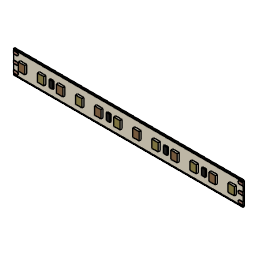
Key Light Housing (Autodesk Fusion 360 archive; units mm, degrees)
design "Yuji LED Single Strip"
Autodesk Fusion 360 part; units mm, degrees
sketch "Sketch1" plane through (0, 0, 0) normal (0, 1, 0) x (1, 0, 0)
  line L0 (0, 0) -> (100, 0)
  line L1 (100, 0) -> (100, -10)
  line L2 (100, -10) -> (0, -10)
  line L3 (0, -10) -> (0, 0)
  line L4 (2.95, -6.75) -> (5.75, -6.75)
  line L5 (5.75, -6.75) -> (5.75, -3.25)
  line L6 (5.75, -3.25) -> (2.95, -3.25)
  line L7 (2.95, -3.25) -> (2.95, -6.75)
  line L8 (11.25, -6.75) -> (14.05, -6.75)
  line L9 (14.05, -6.75) -> (14.05, -3.25)
  line L10 (14.05, -3.25) -> (11.25, -3.25)
  line L11 (11.25, -3.25) -> (11.25, -6.75)
  line L12 (0, -9.25) -> (1.5, -9.25)
  line L13 (1.5, -9.25) -> (1.5, -8) construction
  line L14 (1.5, -8) -> (0, -8)
  line L15 (0, -8) -> (0, -9.25)
  line L16 (0, -2) -> (1.5, -2)
  line L17 (1.5, -2) -> (1.5, -0.75) construction
  line L18 (1.5, -0.75) -> (0, -0.75)
  line L19 (0, -0.75) -> (0, -2)
  arc A0 (1.5, -9.25) -> (1.5, -8) centre (1.5, -8.625) ccw
  arc A1 (1.5, -2) -> (1.5, -0.75) centre (1.5, -1.375) ccw
  line L20 (50, -10) -> (50, 0) construction
  line L21 (0, -4.375) -> (1.5, -4.375)
  arc A2 (1.5, -5.625) -> (1.5, -4.375) centre (1.5, -5) ccw
  line L22 (0, -5.625) -> (0, -4.375)
  line L23 (1.5, -5.625) -> (0, -5.625)
  line L24 (1.5, -4.375) -> (1.5, -5.625) construction
  line L25 (100, -9.25) -> (98.5, -9.25)
  line L26 (98.5, -9.25) -> (98.5, -8) construction
  line L27 (98.5, -8) -> (100, -8)
  line L28 (100, -8) -> (100, -9.25)
  line L29 (98.5, -4.375) -> (100, -4.375)
  line L30 (100, -4.375) -> (100, -5.625)
  line L31 (100, -5.625) -> (98.5, -5.625)
  line L32 (98.5, -5.625) -> (98.5, -4.375) construction
  line L33 (98.5, -0.75) -> (100, -0.75)
  line L34 (100, -0.75) -> (100, -2)
  line L35 (100, -2) -> (98.5, -2)
  line L36 (98.5, -2) -> (98.5, -0.75) construction
  line L37 (0, -5) -> (2.95, -5) construction
  line L38 (5.75, -5) -> (11.25, -5) construction
  line L39 (19.55, -6.75) -> (22.35, -6.75)
  line L40 (22.35, -6.75) -> (22.35, -3.25)
  line L41 (22.35, -3.25) -> (19.55, -3.25)
  line L42 (19.55, -3.25) -> (19.55, -6.75)
  line L43 (27.85, -6.75) -> (30.65, -6.75)
  line L44 (30.65, -6.75) -> (30.65, -3.25)
  line L45 (30.65, -3.25) -> (27.85, -3.25)
  line L46 (27.85, -3.25) -> (27.85, -6.75)
  line L47 (36.15, -6.75) -> (38.95, -6.75)
  line L48 (38.95, -6.75) -> (38.95, -3.25)
  line L49 (38.95, -3.25) -> (36.15, -3.25)
  line L50 (36.15, -3.25) -> (36.15, -6.75)
  line L51 (14.05, -5) -> (19.55, -5) construction
  line L52 (22.35, -5) -> (27.85, -5) construction
  line L53 (30.65, -5) -> (36.15, -5) construction
  line L54 (72.15, -5) -> (77.65, -5) construction
  line L55 (80.45, -3.25) -> (77.65, -3.25)
  line L56 (69.35, -3.25) -> (69.35, -6.75)
  line L57 (44.45, -6.75) -> (47.25, -6.75)
  line L58 (52.75, -6.75) -> (55.55, -6.75)
  line L59 (55.55, -3.25) -> (52.75, -3.25)
  line L60 (63.85, -5) -> (69.35, -5) construction
  line L61 (47.25, -6.75) -> (47.25, -3.25)
  line L62 (77.65, -6.75) -> (80.45, -6.75)
  line L63 (52.75, -3.25) -> (52.75, -6.75)
  line L64 (61.05, -3.25) -> (61.05, -6.75)
  line L65 (44.45, -3.25) -> (44.45, -6.75)
  line L66 (63.85, -3.25) -> (61.05, -3.25)
  line L67 (61.05, -6.75) -> (63.85, -6.75)
  line L68 (72.15, -3.25) -> (69.35, -3.25)
  line L69 (63.85, -6.75) -> (63.85, -3.25)
  line L70 (72.15, -6.75) -> (72.15, -3.25)
  line L71 (80.45, -6.75) -> (80.45, -3.25)
  line L72 (77.65, -3.25) -> (77.65, -6.75)
  line L73 (55.55, -6.75) -> (55.55, -3.25)
  line L74 (69.35, -6.75) -> (72.15, -6.75)
  line L75 (47.25, -5) -> (52.75, -5) construction
  line L76 (47.25, -3.25) -> (44.45, -3.25)
  line L77 (55.55, -5) -> (61.05, -5) construction
  line L78 (38.95, -5) -> (44.45, -5) construction
  line L79 (97.05, -6.75) -> (97.05, -3.25)
  line L80 (88.75, -5) -> (94.25, -5) construction
  line L81 (85.95, -6.75) -> (88.75, -6.75)
  line L82 (94.25, -6.75) -> (97.05, -6.75)
  line L83 (97.05, -3.25) -> (94.25, -3.25)
  line L84 (88.75, -6.75) -> (88.75, -3.25)
  line L85 (85.95, -3.25) -> (85.95, -6.75)
  line L86 (94.25, -3.25) -> (94.25, -6.75)
  line L87 (88.75, -3.25) -> (85.95, -3.25)
  line L88 (80.45, -5) -> (85.95, -5) construction
  line L89 (97.05, -5) -> (100, -5) construction
  line L90 (16, -6.5) -> (17.6, -6.5)
  line L91 (17.6, -6.5) -> (17.6, -3.5)
  line L92 (17.6, -3.5) -> (16, -3.5)
  line L93 (16, -3.5) -> (16, -6.5)
  line L94 (17.6, -5) -> (19.55, -5) construction
  line L95 (16, -5) -> (14.05, -5) construction
  line L96 (40.9, -6.5) -> (42.5, -6.5)
  line L97 (42.5, -6.5) -> (42.5, -3.5)
  line L98 (42.5, -3.5) -> (40.9, -3.5)
  line L99 (40.9, -3.5) -> (40.9, -6.5)
  line L100 (65.8, -6.5) -> (67.4, -6.5)
  line L101 (67.4, -6.5) -> (67.4, -3.5)
  line L102 (67.4, -3.5) -> (65.8, -3.5)
  line L103 (65.8, -3.5) -> (65.8, -6.5)
  line L104 (82.4, -6.5) -> (84, -6.5)
  line L105 (84, -6.5) -> (84, -3.5)
  line L106 (84, -3.5) -> (82.4, -3.5)
  line L107 (82.4, -3.5) -> (82.4, -6.5)
  line L108 (84, -5) -> (85.95, -5) construction
  line L109 (82.4, -5) -> (80.45, -5) construction
  line L110 (67.4, -5) -> (69.35, -5) construction
  line L111 (65.8, -5) -> (63.85, -5) construction
  line L112 (42.5, -5) -> (44.45, -5) construction
  line L113 (40.9, -5) -> (38.95, -5) construction
  arc A3 (98.5, -8) -> (98.5, -9.25) centre (98.5, -8.625) ccw
  arc A4 (98.5, -4.375) -> (98.5, -5.625) centre (98.5, -5) ccw
  arc A5 (98.5, -0.75) -> (98.5, -2) centre (98.5, -1.375) ccw
  line L114 (0, -10) -> (100, -10)
  line L115 (100, -10) -> (100, -9.7)
  line L116 (100, -9.7) -> (0, -9.7)
  line L117 (0, -9.7) -> (0, -10)
  line L118 (100, 0) -> (0, 0)
  line L119 (0, 0) -> (0, -0.3)
  line L120 (0, -0.3) -> (100, -0.3)
  line L121 (100, -0.3) -> (100, 0)
  point P0 (44.45, -5)
  point P1 (85.95, -5)
  dimension "d1" = 100
  dimension "d2" = 10
  dimension "d3" = 1.5
  dimension "d4" = 0.75
  dimension "d5" = 1.25
  dimension "d6" = 0.75
  dimension "d13" = 2.8
  dimension "d14" = 3.5
  dimension "d17" = 5.5
  dimension "d19" = 1.6
  dimension "d20" = 3
  dimension "d29" = 0.3
  dimension "d30" = 0.3
  constraint horizontal L0
  constraint vertical L1
  constraint horizontal L2
  constraint vertical L3
  constraint coincident L0.start L3.end
  constraint horizontal L4
  constraint vertical L5
  constraint horizontal L6
  constraint vertical L7
  constraint horizontal L8
  constraint vertical L9
  constraint horizontal L10
  constraint vertical L11
  constraint horizontal L12
  constraint vertical L13
  constraint horizontal L14
  constraint vertical L15
  constraint coincident L3 L12.start
  constraint horizontal L16
  constraint vertical L17
  constraint horizontal L18
  constraint vertical L19
  constraint coincident L3 L16.start
  constraint midpoint L13 A0.centre
  constraint midpoint L17 A1.centre
  constraint midpoint L2 L20.start
  constraint midpoint L0 L20.end
  constraint horizontal L21
  constraint vertical L24
  constraint horizontal L23
  constraint vertical L22
  constraint midpoint A2.centre L24
  constraint horizontal L25
  constraint vertical L26
  constraint horizontal L27
  constraint vertical L28
  constraint coincident L1 L25.start
  constraint equal L12 L25
  constraint collinear L12 L25
  constraint equal L16 L21
  constraint equal L14 L23
  constraint midpoint L3 L22
  constraint equal L17 L24
  constraint equal L13 L24
  constraint equal L13 L26
  constraint horizontal L31
  constraint vertical L32
  constraint horizontal L29
  constraint vertical L30
  constraint horizontal L35
  constraint vertical L36
  constraint horizontal L33
  constraint vertical L34
  constraint midpoint L1 L30
  constraint equal L26 L32
  constraint equal L32 L36
  constraint coincident L1 L33.end
  constraint equal L27 L31
  constraint equal L29 L35
  constraint collinear L18 L33
  constraint midpoint L3 L37.start
  constraint midpoint L7 L37.end
  constraint midpoint L5 L38.start
  constraint horizontal L37
  constraint horizontal L38
  constraint equal L4 L8
  constraint equal L5 L11
  constraint midpoint L11 L38.end
  constraint horizontal L39
  constraint vertical L40
  constraint horizontal L41
  constraint vertical L42
  constraint horizontal L43
  constraint vertical L44
  constraint horizontal L45
  constraint vertical L46
  constraint horizontal L47
  constraint vertical L48
  constraint horizontal L49
  constraint vertical L50
  constraint midpoint L9 L51.start
  constraint midpoint L42 L51.end
  constraint midpoint L40 L52.start
  constraint midpoint L46 L52.end
  constraint equal L8 L39
  constraint equal L39 L43
  constraint equal L43 L47
  constraint horizontal L51
  constraint horizontal L52
  constraint equal L38 L51
  constraint equal L51 L52
  constraint midpoint L44 L53.start
  constraint midpoint L50 L53.end
  constraint horizontal L53
  constraint collinear L8 L39
  constraint collinear L39 L43
  constraint collinear L43 L47
  constraint equal L52 L53
  constraint horizontal L57
  constraint vertical L61
  constraint horizontal L76
  constraint vertical L65
  constraint horizontal L58
  constraint vertical L73
  constraint horizontal L59
  constraint vertical L63
  constraint midpoint P0 L65
  constraint midpoint L75.start L61
  constraint horizontal L75
  constraint equal L57 L58
  constraint equal L61 L63
  constraint midpoint L75.end L63
  constraint horizontal L67
  constraint vertical L69
  constraint horizontal L66
  constraint vertical L64
  constraint horizontal L74
  constraint vertical L70
  constraint horizontal L68
  constraint vertical L56
  constraint horizontal L62
  constraint vertical L71
  constraint horizontal L55
  constraint vertical L72
  constraint midpoint L77.start L73
  constraint midpoint L77.end L64
  constraint midpoint L60.start L69
  constraint midpoint L60.end L56
  constraint equal L58 L67
  constraint equal L67 L74
  constraint equal L62 L74
  constraint horizontal L77
  constraint horizontal L60
  constraint equal L75 L77
  constraint equal L60 L77
  constraint midpoint L54.start L70
  constraint midpoint L54.end L72
  constraint horizontal L54
  constraint collinear L58 L67
  constraint collinear L67 L74
  constraint collinear L62 L74
  constraint equal L54 L60
  constraint midpoint L48 L78.start
  constraint coincident P0 L78.end
  constraint perpendicular L65 L78
  constraint equal L53 L78
  constraint equal L75 L78
  constraint horizontal L81
  constraint vertical L84
  constraint horizontal L87
  constraint vertical L85
  constraint horizontal L82
  constraint vertical L79
  constraint horizontal L83
  constraint vertical L86
  constraint midpoint P1 L85
  constraint equal L81 L82
  constraint midpoint L80.start L84
  constraint midpoint L80.end L86
  constraint horizontal L80
  constraint collinear L81 L82
  constraint midpoint L71 L88.start
  constraint coincident P1 L88.end
  constraint perpendicular L85 L88
  constraint equal L54 L88
  constraint equal L80 L88
  constraint equal L62 L81
  constraint equal L47 L57
  constraint midpoint L79 L89.start
  constraint midpoint L30 L89.end
  constraint equal L37 L89
  constraint collinear L62 L81
  constraint collinear L47 L57
  constraint horizontal L90
  constraint vertical L91
  constraint horizontal L92
  constraint vertical L93
  constraint midpoint L91 L94.start
  constraint midpoint L93 L95.start
  constraint equal L94 L95
  constraint horizontal L95
  constraint horizontal L96
  constraint vertical L97
  constraint horizontal L98
  constraint vertical L99
  constraint equal L90 L96
  constraint equal L91 L99
  constraint horizontal L100
  constraint vertical L101
  constraint horizontal L102
  constraint vertical L103
  constraint horizontal L104
  constraint vertical L105
  constraint horizontal L106
  constraint vertical L107
  constraint equal L96 L100
  constraint equal L97 L103
  constraint equal L100 L104
  constraint equal L101 L107
  constraint midpoint L105 L108.start
  constraint midpoint L107 L109.start
  constraint equal L108 L109
  constraint horizontal L109
  constraint midpoint L101 L110.start
  constraint midpoint L103 L111.start
  constraint equal L110 L111
  constraint horizontal L111
  constraint midpoint L97 L112.start
  constraint midpoint L99 L113.start
  constraint equal L112 L113
  constraint horizontal L113
  constraint midpoint L26 A3.centre
  constraint midpoint L32 A4.centre
  constraint midpoint L36 A5.centre
  constraint horizontal L114
  constraint vertical L115
  constraint horizontal L116
  constraint vertical L117
  constraint coincident L1 L115.end
  constraint horizontal L118
  constraint vertical L119
  constraint horizontal L120
  constraint vertical L121
  measures "d1" distance of L0.start L0.end
  measures "d2" distance of L0.start L2.end
  measures "d3" distance of L12.start L12.end
  measures "d4" distance of L2 L12
  measures "d5" distance of L12.end L13.end
  measures "d6" distance of L0 L18
  measures "d13" distance of L4.start L4.end
  measures "d14" distance of L4.end L5.end
  measures "d17" distance of L38.start L38.end
  measures "d19" distance of L90.start L90.end
  measures "d20" distance of L90.end L91.end
  measures "d29" distance of L2.end L116.end
  measures "d30" distance of L0.end L120.end
extrude "Extrude1" add sketch "Sketch1" along normal blind 0.55 contours L0 L1 L3 L118 L119 L120 L121 | L1 L3 L12 L14 L16 L18 A0 A1 L21 A2 L23 L25 L27 L29 L31 L33 L35 A3 A4 A5 L116 L120 | L3 L16 L18 L19 A1 | L1 L33 L34 L35 A5 | L3 L21 A2 L22 L23 | L1 L29 L30 L31 A4 | L3 L12 L14 L15 A0 | L1 L25 L27 L28 A3 | L1 L2 L3 L114 L115 L116 L117 | L4 L5 L6 L7 | L8 L9 L10 L11 | L39 L40 L41 L42 | L43 L44 L45 L46 | L47 L48 L49 L50 | L55 L62 L71 L72 | L56 L68 L70 L74 | L57 L61 L65 L76 | L58 L59 L63 L73 | L64 L66 L67 L69 | L79 L82 L83 L86 | L81 L84 L85 L87 | L90 L91 L92 L93 | L96 L97 L98 L99 | L100 L101 L102 L103 | L104 L105 L106 L107
extrude "Extrude2" add sketch "Sketch1" against normal blind 0.1 contours L0 L1 L3 L118 L119 L120 L121 | L3 L16 L18 L19 A1 | L1 L33 L34 L35 A5 | L3 L21 A2 L22 L23 | L1 L29 L30 L31 A4 | L3 L12 L14 L15 A0 | L1 L25 L27 L28 A3 | L1 L2 L3 L114 L115 L116 L117
extrude "Extrude3" add sketch "Sketch1" against normal blind 0.85 contours L4 L5 L6 L7 | L8 L9 L10 L11 | L39 L40 L41 L42 | L43 L44 L45 L46 | L47 L48 L49 L50 | L55 L62 L71 L72 | L56 L68 L70 L74 | L57 L61 L65 L76 | L58 L59 L63 L73 | L64 L66 L67 L69 | L79 L82 L83 L86 | L81 L84 L85 L87
extrude "Extrude4" add sketch "Sketch1" against normal blind 0.5 contours L90 L91 L92 L93 | L96 L97 L98 L99 | L100 L101 L102 L103 | L104 L105 L106 L107
equation "d25 = -1.4 mm + 0.55 mm"
named bodies: "YJ-BC-HRB-2835-24-2765"
